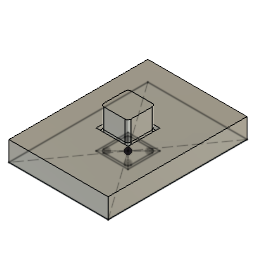
widget_foam_cutter_handle (Autodesk Fusion 360 design; units mm, degrees)
part number: 2025-11-08-19-58-26-787
Autodesk Fusion 360 part; units mm, degrees
sketch "Sketch1" plane through (0, 0, 0) normal (0, 0, 1) x (1, 0, 0)
  line L0 (5.375, 6.875) -> (-5.375, 6.875)
  line L1 (-6.875, 5.375) -> (-6.875, -5.375)
  line L2 (-5.375, -6.875) -> (5.375, -6.875)
  line L3 (6.875, -5.375) -> (6.875, 5.375)
  line L4 (6.875, 6.875) -> (-6.875, -6.875) construction
  line L5 (-6.875, 6.875) -> (6.875, -6.875) construction
  line L6 (8, 8) -> (-8, 8)
  line L7 (-8, 8) -> (-8, -8)
  line L8 (-8, -8) -> (8, -8)
  line L9 (8, -8) -> (8, 8)
  line L10 (8, 8) -> (-8, -8) construction
  line L11 (-8, 8) -> (8, -8) construction
  line L12 (25, 35) -> (-25, 35)
  line L13 (-25, 35) -> (-25, -35)
  line L14 (-25, -35) -> (25, -35)
  line L15 (25, -35) -> (25, 35)
  line L16 (25, 35) -> (-25, -35) construction
  line L17 (-25, 35) -> (25, -35) construction
  arc A0 (-5.375, 6.875) -> (-6.875, 5.375) centre (-5.375, 5.375) ccw
  arc A1 (6.875, 5.375) -> (5.375, 6.875) centre (5.375, 5.375) ccw
  arc A2 (-6.875, -5.375) -> (-5.375, -6.875) centre (-5.375, -5.375) ccw
  arc A3 (5.375, -6.875) -> (6.875, -5.375) centre (5.375, -5.375) ccw
  dimension "d1" = 13.75
  dimension "d2" = 13.75
  dimension "d3" = 16
  dimension "d4" = 16
  dimension "d5" = 50
  dimension "d6" = 70
  dimension "d14" = 1.5
  dimension "d15" = 1.5
  dimension "d16" = 1.5
  dimension "d17" = 1.5
  constraint horizontal L0
  constraint perpendicular L0 L1
  constraint parallel L0 L2
  constraint parallel L1 L3
  constraint coincident L4 origin
  constraint coincident L5 origin
  constraint horizontal L6
  constraint perpendicular L6 L7
  constraint parallel L6 L8
  constraint parallel L7 L9
  constraint coincident L10 origin
  constraint coincident L11 origin
  constraint horizontal L12
  constraint perpendicular L12 L13
  constraint parallel L12 L14
  constraint parallel L13 L15
  constraint coincident L16 origin
  constraint coincident L17 origin
  constraint coincident L5.start L0
  constraint coincident L5.start L1
  constraint tangent L0 A0
  constraint tangent L1 A0
  constraint coincident L4.start L0
  constraint coincident L4.start L3
  constraint tangent L0 A1
  constraint tangent L3 A1
  constraint coincident L4.end L1
  constraint coincident L4.end L2
  constraint tangent L1 A2
  constraint tangent L2 A2
  constraint coincident L5.end L2
  constraint coincident L5.end L3
  constraint tangent L2 A3
  constraint tangent L3 A3
  measures "d1" distance of L4.end L5.end
  measures "d2" distance of L5.start L4.end
  measures "d3" distance of L7.end L8.end
  measures "d4" distance of L6.end L7.end
  measures "d5" distance of L13.end L14.end
  measures "d6" distance of L12.end L13.end
  measures "d14" radius of A0
  measures "d15" radius of A1
  measures "d16" radius of A2
  measures "d17" radius of A3
extrude "Extrude1" add sketch "Sketch1" along normal blind 10 contours L0 L1 L2 L3 A0 A1 A2 A3 | L6 L7 L8 L9 | L12 L13 L14 L15 makes body 1
extrude "Extrude2" add sketch "Sketch1" along normal blind 20 separate body contours L0 L1 L2 L3 A0 A1 A2 A3 makes body 2
extrude "Extrude3" cut sketch "Sketch1" along normal blind 2 from surface at 8 contours L6 L7 L8 L9 bodies 1
